Autodesk Fusion 360 part; units mm, degrees
(part 4 of 8)
  spline S80 degree 3 poles (3.437205, 4.752057) (3.428553, 4.734546) (3.423403, 4.715512) (3.42069, 4.676542) (3.423152, 4.656979) (3.435437, 4.619896) (3.445142, 4.602732) (3.470585, 4.573089) (3.48608, 4.560895) (3.520872, 4.543132) (3.539837, 4.537733) (3.578768, 4.534508) (3.598362, 4.536713) (3.62701, 4.545788) (3.636675, 4.55001) (3.654962, 4.560407) (3.663534, 4.566553) (3.671392, 4.573544) knots 0 0 0 0 0.00585967 0.00585967 0.01171933 0.01171933 0.017579 0.017579 0.02343867 0.02343867 0.02929834 0.02929834 0.035158 0.035158 0.03831344 0.03831344 0.04146887 0.04146887 0.04146887 0.04146887
  spline S81 degree 5 poles (3.437205, 4.752057) (3.437297, 4.752244) (3.438255, 4.754183) (3.440069, 4.75788) (3.442718, 4.763351) (3.446163, 4.770621) (3.45027, 4.779531) (3.454293, 4.788497) (3.458241, 4.797513) (3.462123, 4.806574) (3.465948, 4.815673) (3.469718, 4.824809) (3.473434, 4.833981) (3.477094, 4.843189) (3.480698, 4.852435) (3.484243, 4.861719) (3.48773, 4.871041) (3.491161, 4.8804) (3.494537, 4.889793) (3.49786, 4.89922) (3.501134, 4.908679) (3.504358, 4.91817) (3.507533, 4.927692) (3.510659, 4.937244) (3.513737, 4.946827) (3.516767, 4.956439) (3.519748, 4.966082) (3.522682, 4.975754) (3.525569, 4.985455) (3.528411, 4.995184) (3.531207, 5.00494) (3.533958, 5.014723) (3.536665, 5.024534) (3.539327, 5.03437) (3.541946, 5.044233) (3.544521, 5.054122) (3.547053, 5.064037) (3.549542, 5.073976) (3.551988, 5.083941) (3.554392, 5.09393) (3.556754, 5.103943) (3.559075, 5.11398) (3.561354, 5.124041) (3.563592, 5.134125) (3.565789, 5.144233) (3.567945, 5.154363) (3.570062, 5.164516) (3.572137, 5.174692) (3.574173, 5.18489) (3.576169, 5.195109) (3.578126, 5.20535) (3.580043, 5.215613) (3.581921, 5.225897) (3.58376, 5.236202) (3.58556, 5.246528) (3.587321, 5.256875) (3.589044, 5.267242) (3.590728, 5.277629) (3.592375, 5.288036) (3.593983, 5.298463) (3.595553, 5.30891) (3.597086, 5.319376) (3.59858, 5.329861) (3.599746, 5.338265) (3.600604, 5.344576) (3.601168, 5.348788) (3.601448, 5.350894) knots 0.1270499 0.1270499 0.1270499 0.1270499 0.1270499 0.1270499 0.12857143 0.14285714 0.15714286 0.17142857 0.18571429 0.2 0.21428571 0.22857143 0.24285714 0.25714286 0.27142857 0.28571429 0.3 0.31428571 0.32857143 0.34285714 0.35714286 0.37142857 0.38571429 0.4 0.41428571 0.42857143 0.44285714 0.45714286 0.47142857 0.48571429 0.5 0.51428571 0.52857143 0.54285714 0.55714286 0.57142857 0.58571429 0.6 0.61428571 0.62857143 0.64285714 0.65714286 0.67142857 0.68571429 0.7 0.71428571 0.72857143 0.74285714 0.75714286 0.77142857 0.78571429 0.8 0.81428571 0.82857143 0.84285714 0.85714286 0.87142857 0.88571429 0.9 0.91428571 0.92857143 0.94285714 0.95714286 0.97142857 0.98571429 1 1 1 1 1 1
  arc A27 (3.601448, 5.350894) -> (3.409471, 5.475218) centre (0, 0) ccw
  spline S82 degree 5 poles (3.409471, 5.475218) (3.407663, 5.4741) (3.404051, 5.471863) (3.398643, 5.468498) (3.391451, 5.463997) (3.382495, 5.458343) (3.373571, 5.452664) (3.364681, 5.446957) (3.355824, 5.441224) (3.347001, 5.435465) (3.338212, 5.429679) (3.329457, 5.423866) (3.320736, 5.418026) (3.31205, 5.41216) (3.303398, 5.406266) (3.294782, 5.400346) (3.286202, 5.394398) (3.277657, 5.388424) (3.269148, 5.382422) (3.260676, 5.376392) (3.25224, 5.370336) (3.243841, 5.364252) (3.235479, 5.35814) (3.227154, 5.352) (3.218868, 5.345833) (3.21062, 5.339637) (3.20241, 5.333414) (3.194239, 5.327162) (3.186107, 5.320882) (3.178016, 5.314574) (3.169964, 5.308237) (3.161952, 5.301871) (3.153982, 5.295476) (3.146054, 5.289052) (3.138167, 5.282598) (3.130322, 5.276115) (3.12252, 5.269603) (3.114761, 5.26306) (3.107046, 5.256488) (3.099375, 5.249885) (3.091749, 5.243251) (3.08417, 5.236586) (3.076637, 5.22989) (3.069152, 5.223161) (3.061715, 5.216401) (3.054325, 5.209608) (3.046984, 5.202784) (3.039691, 5.195928) (3.032449, 5.189038) (3.025258, 5.182115) (3.018122, 5.175157) (3.011042, 5.168161) (3.00402, 5.161129) (2.997057, 5.154058) (2.990152, 5.146951) (2.983303, 5.139808) (2.976508, 5.13263) (2.96977, 5.125418) (2.963091, 5.118169) (2.956478, 5.110879) (2.949942, 5.10354) (2.943491, 5.096148) (2.938267, 5.09003) (2.934359, 5.085375) (2.931727, 5.082207) (2.930349, 5.08054) (2.930217, 5.08038) knots -1 -1 -1 -1 -1 -1 -0.98571429 -0.97142857 -0.95714286 -0.94285714 -0.92857143 -0.91428571 -0.9 -0.88571429 -0.87142857 -0.85714286 -0.84285714 -0.82857143 -0.81428571 -0.8 -0.78571429 -0.77142857 -0.75714286 -0.74285714 -0.72857143 -0.71428571 -0.7 -0.68571429 -0.67142857 -0.65714286 -0.64285714 -0.62857143 -0.61428571 -0.6 -0.58571429 -0.57142857 -0.55714286 -0.54285714 -0.52857143 -0.51428571 -0.5 -0.48571429 -0.47142857 -0.45714286 -0.44285714 -0.42857143 -0.41428571 -0.4 -0.38571429 -0.37142857 -0.35714286 -0.34285714 -0.32857143 -0.31428571 -0.3 -0.28571429 -0.27142857 -0.25714286 -0.24285714 -0.22857143 -0.21428571 -0.2 -0.18571429 -0.17142857 -0.15714286 -0.14285714 -0.12857143 -0.1270499 -0.1270499 -0.1270499 -0.1270499 -0.1270499 -0.1270499
  spline S83 degree 3 poles (2.671525, 5.221052) (2.665646, 5.202425) (2.663463, 5.182829) (2.66673, 5.143901) (2.672149, 5.124942) (2.689951, 5.09017) (2.702162, 5.074688) (2.731833, 5.049277) (2.749007, 5.039591) (2.786103, 5.027347) (2.80567, 5.024906) (2.844637, 5.027662) (2.863665, 5.032832) (2.890591, 5.046174) (2.899499, 5.051822) (2.915985, 5.064889) (2.923518, 5.072271) (2.930217, 5.08038) knots 0 0 0 0 0.00585967 0.00585967 0.01171933 0.01171933 0.017579 0.017579 0.02343867 0.02343867 0.02929834 0.02929834 0.035158 0.035158 0.03831344 0.03831344 0.04146887 0.04146887 0.04146887 0.04146887
  spline S84 degree 5 poles (2.671525, 5.221052) (2.671587, 5.221251) (2.672237, 5.223313) (2.673466, 5.227244) (2.675248, 5.233055) (2.677544, 5.240765) (2.680242, 5.250198) (2.682849, 5.259673) (2.685375, 5.269187) (2.687828, 5.278733) (2.690219, 5.28831) (2.69255, 5.297914) (2.694823, 5.307546) (2.697035, 5.317205) (2.699185, 5.326893) (2.701271, 5.336609) (2.703294, 5.346354) (2.705256, 5.356127) (2.707159, 5.365925) (2.709004, 5.375749) (2.710796, 5.385597) (2.712533, 5.395469) (2.714218, 5.405364) (2.715849, 5.415281) (2.717428, 5.425221) (2.718955, 5.435184) (2.720429, 5.445169) (2.721852, 5.455175) (2.723225, 5.465203) (2.724548, 5.475251) (2.725822, 5.48532) (2.727047, 5.495409) (2.728225, 5.505518) (2.729355, 5.515646) (2.730437, 5.525793) (2.731472, 5.535959) (2.732461, 5.546143) (2.733404, 5.556346) (2.7343, 5.566567) (2.735151, 5.576806) (2.735957, 5.587063) (2.736718, 5.597337) (2.737435, 5.607628) (2.738107, 5.617935) (2.738736, 5.62826) (2.739321, 5.638601) (2.739862, 5.648958) (2.74036, 5.659331) (2.740816, 5.66972) (2.741228, 5.680124) (2.741599, 5.690544) (2.741927, 5.700979) (2.742213, 5.711429) (2.742457, 5.721894) (2.74266, 5.732374) (2.742821, 5.742868) (2.742941, 5.753377) (2.74302, 5.763899) (2.743058, 5.774436) (2.743056, 5.784986) (2.743013, 5.79555) (2.74293, 5.806127) (2.742807, 5.816718) (2.742677, 5.825201) (2.742561, 5.83157) (2.742475, 5.835818) (2.742431, 5.837943) knots 0.1270499 0.1270499 0.1270499 0.1270499 0.1270499 0.1270499 0.12857143 0.14285714 0.15714286 0.17142857 0.18571429 0.2 0.21428571 0.22857143 0.24285714 0.25714286 0.27142857 0.28571429 0.3 0.31428571 0.32857143 0.34285714 0.35714286 0.37142857 0.38571429 0.4 0.41428571 0.42857143 0.44285714 0.45714286 0.47142857 0.48571429 0.5 0.51428571 0.52857143 0.54285714 0.55714286 0.57142857 0.58571429 0.6 0.61428571 0.62857143 0.64285714 0.65714286 0.67142857 0.68571429 0.7 0.71428571 0.72857143 0.74285714 0.75714286 0.77142857 0.78571429 0.8 0.81428571 0.82857143 0.84285714 0.85714286 0.87142857 0.88571429 0.9 0.91428571 0.92857143 0.94285714 0.95714286 0.97142857 0.98571429 1 1 1 1 1 1
  arc A28 (2.742431, 5.837943) -> (2.533725, 5.931504) centre (0, 0) ccw
  spline S85 degree 5 poles (2.533725, 5.931504) (2.532109, 5.930123) (2.528881, 5.927361) (2.52405, 5.92321) (2.517629, 5.917664) (2.509641, 5.910709) (2.501689, 5.903734) (2.493774, 5.896737) (2.485896, 5.88972) (2.478056, 5.882681) (2.470253, 5.875621) (2.462488, 5.86854) (2.45476, 5.861437) (2.447072, 5.854314) (2.439421, 5.847169) (2.43181, 5.840002) (2.424238, 5.832815) (2.416705, 5.825606) (2.409212, 5.818375) (2.40176, 5.811123) (2.394347, 5.80385) (2.386975, 5.796555) (2.379644, 5.789238) (2.372355, 5.7819) (2.365107, 5.77454) (2.357901, 5.767158) (2.350737, 5.759754) (2.343616, 5.752329) (2.336539, 5.744881) (2.329505, 5.737411) (2.322515, 5.729919) (2.315569, 5.722405) (2.308668, 5.714868) (2.301813, 5.707309) (2.295004, 5.699727) (2.288241, 5.692123) (2.281524, 5.684496) (2.274855, 5.676846) (2.268233, 5.669172) (2.26166, 5.661476) (2.255137, 5.653756) (2.248664, 5.646012) (2.242242, 5.638244) (2.235871, 5.630452) (2.229553, 5.622635) (2.223287, 5.614794) (2.217073, 5.606929) (2.210913, 5.59904) (2.204807, 5.591126) (2.198757, 5.583186) (2.192767, 5.57522) (2.186838, 5.567226) (2.180972, 5.559204) (2.17517, 5.551153) (2.16943, 5.543075) (2.163752, 5.534971) (2.158133, 5.52684) (2.152574, 5.518684) (2.147079, 5.5105) (2.141658, 5.502286) (2.136318, 5.494035) (2.131072, 5.485745) (2.126843, 5.478901) (2.12369, 5.473704) (2.121573, 5.470172) (2.120466, 5.468314) (2.120359, 5.468135) knots -1 -1 -1 -1 -1 -1 -0.98571429 -0.97142857 -0.95714286 -0.94285714 -0.92857143 -0.91428571 -0.9 -0.88571429 -0.87142857 -0.85714286 -0.84285714 -0.82857143 -0.81428571 -0.8 -0.78571429 -0.77142857 -0.75714286 -0.74285714 -0.72857143 -0.71428571 -0.7 -0.68571429 -0.67142857 -0.65714286 -0.64285714 -0.62857143 -0.61428571 -0.6 -0.58571429 -0.57142857 -0.55714286 -0.54285714 -0.52857143 -0.51428571 -0.5 -0.48571429 -0.47142857 -0.45714286 -0.44285714 -0.42857143 -0.41428571 -0.4 -0.38571429 -0.37142857 -0.35714286 -0.34285714 -0.32857143 -0.31428571 -0.3 -0.28571429 -0.27142857 -0.25714286 -0.24285714 -0.22857143 -0.21428571 -0.2 -0.18571429 -0.17142857 -0.15714286 -0.14285714 -0.12857143 -0.1270499 -0.1270499 -0.1270499 -0.1270499 -0.1270499 -0.1270499
  spline S86 degree 3 poles (1.843226, 5.56767) (1.84026, 5.548364) (1.841093, 5.528664) (1.850264, 5.490691) (1.858514, 5.472782) (1.881415, 5.441134) (1.895847, 5.427698) (1.929048, 5.407114) (1.9475, 5.400163) (1.986031, 5.393725) (2.00574, 5.3943) (2.04383, 5.402972) (2.061846, 5.410986) (2.08642, 5.428282) (2.094361, 5.435223) (2.108659, 5.450653) (2.114977, 5.459099) (2.120359, 5.468135) knots 0 0 0 0 0.00585967 0.00585967 0.01171933 0.01171933 0.017579 0.017579 0.02343867 0.02343867 0.02929834 0.02929834 0.035158 0.035158 0.03831344 0.03831344 0.04146887 0.04146887 0.04146887 0.04146887
  spline S87 degree 5 poles (1.843226, 5.56767) (1.843257, 5.567876) (1.843585, 5.570013) (1.844199, 5.574086) (1.845073, 5.580101) (1.846165, 5.588071) (1.847392, 5.597805) (1.848522, 5.607567) (1.849566, 5.617354) (1.850533, 5.627164) (1.851434, 5.636993) (1.852272, 5.64684) (1.853048, 5.656706) (1.853759, 5.66659) (1.854405, 5.676493) (1.854984, 5.686414) (1.855496, 5.696353) (1.855943, 5.706311) (1.856327, 5.716285) (1.856652, 5.726275) (1.856919, 5.736281) (1.857129, 5.746303) (1.857283, 5.756338) (1.857382, 5.766389) (1.857425, 5.776453) (1.857413, 5.786532) (1.857346, 5.796625) (1.857225, 5.806732) (1.857051, 5.816851) (1.856824, 5.826984) (1.856546, 5.837129) (1.856217, 5.847287) (1.855838, 5.857457) (1.855408, 5.867639) (1.854929, 5.877832) (1.854401, 5.888037) (1.853823, 5.898253) (1.853197, 5.90848) (1.852523, 5.918719) (1.851801, 5.928968) (1.851032, 5.939227) (1.850216, 5.949496) (1.849353, 5.959776) (1.848444, 5.970066) (1.847489, 5.980365) (1.846489, 5.990674) (1.845443, 6.000992) (1.844352, 6.01132) (1.843216, 6.021657) (1.842035, 6.032002) (1.840811, 6.042356) (1.839542, 6.052719) (1.83823, 6.063091) (1.836874, 6.07347) (1.835474, 6.083858) (1.834032, 6.094254) (1.832546, 6.104658) (1.831018, 6.115069) (1.829447, 6.125488) (1.827835, 6.135914) (1.82618, 6.146348) (1.824483, 6.156788) (1.822745, 6.167236) (1.821321, 6.1756) (1.820234, 6.181876) (1.819501, 6.186061) (1.819133, 6.188155) knots 0.1270499 0.1270499 0.1270499 0.1270499 0.1270499 0.1270499 0.12857143 0.14285714 0.15714286 0.17142857 0.18571429 0.2 0.21428571 0.22857143 0.24285714 0.25714286 0.27142857 0.28571429 0.3 0.31428571 0.32857143 0.34285714 0.35714286 0.37142857 0.38571429 0.4 0.41428571 0.42857143 0.44285714 0.45714286 0.47142857 0.48571429 0.5 0.51428571 0.52857143 0.54285714 0.55714286 0.57142857 0.58571429 0.6 0.61428571 0.62857143 0.64285714 0.65714286 0.67142857 0.68571429 0.7 0.71428571 0.72857143 0.74285714 0.75714286 0.77142857 0.78571429 0.8 0.81428571 0.82857143 0.84285714 0.85714286 0.87142857 0.88571429 0.9 0.91428571 0.92857143 0.94285714 0.95714286 0.97142857 0.98571429 1 1 1 1 1 1
  arc A29 (1.819133, 6.188155) -> (1.598591, 6.24876) centre (0, 0) ccw
  spline S88 degree 5 poles (1.598591, 6.24876) (1.597205, 6.247149) (1.594436, 6.243926) (1.590295, 6.239087) (1.584797, 6.232625) (1.577963, 6.224533) (1.57117, 6.216426) (1.564416, 6.208303) (1.557701, 6.200165) (1.551027, 6.192012) (1.544393, 6.183843) (1.5378, 6.17566) (1.531247, 6.167461) (1.524736, 6.159247) (1.518266, 6.151018) (1.511838, 6.142774) (1.505452, 6.134515) (1.499108, 6.12624) (1.492807, 6.117951) (1.486548, 6.109646) (1.480333, 6.101326) (1.474161, 6.092992) (1.468033, 6.084642) (1.461949, 6.076277) (1.455909, 6.067896) (1.449915, 6.059501) (1.443965, 6.051091) (1.438061, 6.042665) (1.432203, 6.034224) (1.426392, 6.025768) (1.420628, 6.017297) (1.41491, 6.008811) (1.409241, 6.000309) (1.40362, 5.991792) (1.398048, 5.98326) (1.392525, 5.974712) (1.387052, 5.966149) (1.381628, 5.95757) (1.376255, 5.948976) (1.370934, 5.940367) (1.365666, 5.931741) (1.360451, 5.9231) (1.35529, 5.914443) (1.350183, 5.905769) (1.345132, 5.89708) (1.340136, 5.888375) (1.335196, 5.879653) (1.330312, 5.870916) (1.325486, 5.862163) (1.320719, 5.853393) (1.316015, 5.844605) (1.311376, 5.8358) (1.306803, 5.826976) (1.302298, 5.818134) (1.297859, 5.809275) (1.293484, 5.800398) (1.289172, 5.791505) (1.284924, 5.782596) (1.280743, 5.77367) (1.276638, 5.764724) (1.272621, 5.755755) (1.268701, 5.746761) (1.265567, 5.739352) (1.263245, 5.733735) (1.261691, 5.72992) (1.260881, 5.727916) (1.260803, 5.727723) knots -1 -1 -1 -1 -1 -1 -0.98571429 -0.97142857 -0.95714286 -0.94285714 -0.92857143 -0.91428571 -0.9 -0.88571429 -0.87142857 -0.85714286 -0.84285714 -0.82857143 -0.81428571 -0.8 -0.78571429 -0.77142857 -0.75714286 -0.74285714 -0.72857143 -0.71428571 -0.7 -0.68571429 -0.67142857 -0.65714286 -0.64285714 -0.62857143 -0.61428571 -0.6 -0.58571429 -0.57142857 -0.55714286 -0.54285714 -0.52857143 -0.51428571 -0.5 -0.48571429 -0.47142857 -0.45714286 -0.44285714 -0.42857143 -0.41428571 -0.4 -0.38571429 -0.37142857 -0.35714286 -0.34285714 -0.32857143 -0.31428571 -0.3 -0.28571429 -0.27142857 -0.25714286 -0.24285714 -0.22857143 -0.21428571 -0.2 -0.18571429 -0.17142857 -0.15714286 -0.14285714 -0.12857143 -0.1270499 -0.1270499 -0.1270499 -0.1270499 -0.1270499 -0.1270499
  spline S89 degree 3 poles (0.971723, 5.783786) (0.971739, 5.764254) (0.97557, 5.744912) (0.99043, 5.708784) (1.001317, 5.692344) (1.02878, 5.664563) (1.045094, 5.653487) (1.081048, 5.638213) (1.100345, 5.63416) (1.139407, 5.633679) (1.158798, 5.637256) (1.195117, 5.65164) (1.211699, 5.662311) (1.233345, 5.683155) (1.240133, 5.691227) (1.251908, 5.708659) (1.256863, 5.71797) (1.260803, 5.727723) knots 0 0 0 0 0.00585967 0.00585967 0.01171933 0.01171933 0.017579 0.017579 0.02343867 0.02343867 0.02929834 0.02929834 0.035158 0.035158 0.03831344 0.03831344 0.04146887 0.04146887 0.04146887 0.04146887
  spline S90 degree 5 poles (0.971723, 5.783786) (0.971723, 5.783994) (0.97172, 5.786157) (0.971705, 5.790275) (0.971652, 5.796353) (0.971514, 5.804397) (0.97124, 5.814204) (0.970867, 5.824024) (0.970404, 5.833856) (0.969863, 5.843698) (0.969253, 5.85355) (0.968578, 5.86341) (0.967839, 5.873278) (0.967033, 5.883155) (0.96616, 5.89304) (0.965217, 5.902933) (0.964206, 5.912834) (0.963128, 5.922743) (0.961985, 5.932659) (0.960781, 5.942582) (0.959517, 5.952512) (0.958195, 5.962448) (0.956816, 5.972389) (0.955379, 5.982337) (0.953885, 5.99229) (0.952335, 6.002249) (0.950728, 6.012214) (0.949065, 6.022183) (0.947349, 6.032158) (0.945578, 6.042137) (0.943755, 6.052121) (0.941879, 6.06211) (0.939952, 6.072102) (0.937973, 6.082099) (0.935943, 6.0921) (0.933863, 6.102105) (0.931733, 6.112113) (0.929553, 6.122125) (0.927324, 6.13214) (0.925046, 6.142159) (0.92272, 6.15218) (0.920346, 6.162205) (0.917924, 6.172233) (0.915455, 6.182263) (0.912939, 6.192296) (0.910377, 6.202331) (0.907768, 6.212369) (0.905113, 6.222409) (0.902413, 6.232451) (0.899667, 6.242495) (0.896876, 6.252541) (0.89404, 6.262589) (0.89116, 6.272638) (0.888235, 6.282689) (0.885267, 6.292742) (0.882254, 6.302795) (0.879198, 6.31285) (0.876098, 6.322907) (0.872956, 6.332964) (0.86977, 6.343022) (0.866542, 6.35308) (0.863272, 6.363139) (0.859959, 6.373199) (0.857275, 6.381248) (0.855243, 6.387284) (0.85388, 6.391309) (0.853196, 6.393321) knots 0.1270499 0.1270499 0.1270499 0.1270499 0.1270499 0.1270499 0.12857143 0.14285714 0.15714286 0.17142857 0.18571429 0.2 0.21428571 0.22857143 0.24285714 0.25714286 0.27142857 0.28571429 0.3 0.31428571 0.32857143 0.34285714 0.35714286 0.37142857 0.38571429 0.4 0.41428571 0.42857143 0.44285714 0.45714286 0.47142857 0.48571429 0.5 0.51428571 0.52857143 0.54285714 0.55714286 0.57142857 0.58571429 0.6 0.61428571 0.62857143 0.64285714 0.65714286 0.67142857 0.68571429 0.7 0.71428571 0.72857143 0.74285714 0.75714286 0.77142857 0.78571429 0.8 0.81428571 0.82857143 0.84285714 0.85714286 0.87142857 0.88571429 0.9 0.91428571 0.92857143 0.94285714 0.95714286 0.97142857 0.98571429 1 1 1 1 1 1
  arc A30 (0.853196, 6.393321) -> (0.625988, 6.419551) centre (0, 0) ccw
  spline S91 degree 5 poles (0.625988, 6.419551) (0.624864, 6.417748) (0.622619, 6.41414) (0.619265, 6.408725) (0.614818, 6.4015) (0.6093, 6.392459) (0.603823, 6.38341) (0.598388, 6.374351) (0.592995, 6.365284) (0.587643, 6.356207) (0.582334, 6.347122) (0.577067, 6.338028) (0.571843, 6.328925) (0.566662, 6.319813) (0.561524, 6.310693) (0.55643, 6.301564) (0.551379, 6.292427) (0.546373, 6.283281) (0.541411, 6.274127) (0.536493, 6.264964) (0.531621, 6.255793) (0.526793, 6.246614) (0.522012, 6.237426) (0.517276, 6.228231) (0.512587, 6.219027) (0.507944, 6.209815) (0.503348, 6.200595) (0.498799, 6.191367) (0.494299, 6.182131) (0.489846, 6.172887) (0.485442, 6.163635) (0.481088, 6.154375) (0.476783, 6.145108) (0.472528, 6.135832) (0.468323, 6.126549) (0.46417, 6.117259) (0.460068, 6.107961) (0.456017, 6.098655) (0.452019, 6.089341) (0.448075, 6.08002) (0.444185, 6.070692) (0.44035, 6.061356) (0.436571, 6.052012) (0.432848, 6.042661) (0.429183, 6.033302) (0.425574, 6.023936) (0.422023, 6.014563) (0.41853, 6.005183) (0.415097, 5.995795) (0.411725, 5.9864) (0.408417, 5.976998) (0.405176, 5.967587) (0.402004, 5.958169) (0.398902, 5.948743) (0.395867, 5.93931) (0.392898, 5.929869) (0.389994, 5.920422) (0.387156, 5.910969) (0.384386, 5.901509) (0.381696, 5.892041) (0.379095, 5.882565) (0.376594, 5.873077) (0.374627, 5.865277) (0.373189, 5.859371) (0.372236, 5.855364) (0.371741, 5.853259) (0.371694, 5.853057) knots -1 -1 -1 -1 -1 -1 -0.98571429 -0.97142857 -0.95714286 -0.94285714 -0.92857143 -0.91428571 -0.9 -0.88571429 -0.87142857 -0.85714286 -0.84285714 -0.82857143 -0.81428571 -0.8 -0.78571429 -0.77142857 -0.75714286 -0.74285714 -0.72857143 -0.71428571 -0.7 -0.68571429 -0.67142857 -0.65714286 -0.64285714 -0.62857143 -0.61428571 -0.6 -0.58571429 -0.57142857 -0.55714286 -0.54285714 -0.52857143 -0.51428571 -0.5 -0.48571429 -0.47142857 -0.45714286 -0.44285714 -0.42857143 -0.41428571 -0.4 -0.38571429 -0.37142857 -0.35714286 -0.34285714 -0.32857143 -0.31428571 -0.3 -0.28571429 -0.27142857 -0.25714286 -0.24285714 -0.22857143 -0.21428571 -0.2 -0.18571429 -0.17142857 -0.15714286 -0.14285714 -0.12857143 -0.1270499 -0.1270499 -0.1270499 -0.1270499 -0.1270499 -0.1270499
  spline S92 degree 3 poles (0.077444, 5.864336) (0.080441, 5.845035) (0.08718, 5.826504) (0.10738, 5.793068) (0.12065, 5.778483) (0.152032, 5.755219) (0.169845, 5.746764) (0.20771, 5.737157) (0.227399, 5.736097) (0.266077, 5.741584) (0.284694, 5.748079) (0.318392, 5.767839) (0.33315, 5.780916) (0.351361, 5.80482) (0.356837, 5.813834) (0.365814, 5.832859) (0.369289, 5.842817) (0.371694, 5.853057) knots 0 0 0 0 0.00585967 0.00585967 0.01171933 0.01171933 0.017579 0.017579 0.02343867 0.02343867 0.02929834 0.02929834 0.035158 0.035158 0.03831344 0.03831344 0.04146887 0.04146887 0.04146887 0.04146887
  spline S93 degree 5 poles (0.077444, 5.864336) (0.077412, 5.864541) (0.07708, 5.866678) (0.076436, 5.870746) (0.075455, 5.876745) (0.074091, 5.884673) (0.072323, 5.894323) (0.070456, 5.903971) (0.068498, 5.913617) (0.066461, 5.923262) (0.064354, 5.932905) (0.062182, 5.942546) (0.059944, 5.952186) (0.057641, 5.961824) (0.055269, 5.97146) (0.052827, 5.981093) (0.050316, 5.990724) (0.047738, 6.000352) (0.045095, 6.009978) (0.04239, 6.0196) (0.039625, 6.029221) (0.036802, 6.038838) (0.033921, 6.048453) (0.030983, 6.058065) (0.027987, 6.067673) (0.024935, 6.077279) (0.021826, 6.086881) (0.018661, 6.09648) (0.015441, 6.106076) (0.012168, 6.115668) (0.008842, 6.125256) (0.005464, 6.134841) (0.002034, 6.144423) (-0.001448, 6.154) (-0.00498, 6.163574) (-0.008563, 6.173144) (-0.012196, 6.18271) (-0.015879, 6.192272) (-0.019611, 6.201829) (-0.023391, 6.211383) (-0.02722, 6.220932) (-0.031097, 6.230477) (-0.035021, 6.240017) (-0.038992, 6.249553) (-0.04301, 6.259084) (-0.047074, 6.268611) (-0.051185, 6.278133) (-0.055341, 6.28765) (-0.059542, 6.297162) (-0.063789, 6.306669) (-0.068081, 6.316171) (-0.072417, 6.325669) (-0.076798, 6.33516) (-0.081223, 6.344647) (-0.085691, 6.354129) (-0.090203, 6.363605) (-0.094758, 6.373075) (-0.099356, 6.382541) (-0.103997, 6.392) (-0.108681, 6.401454) (-0.113406, 6.410902) (-0.118174, 6.420344) (-0.122984, 6.42978) (-0.126865, 6.437325) (-0.129795, 6.44298) (-0.131756, 6.44675) (-0.132739, 6.448634) knots 0.1270499 0.1270499 0.1270499 0.1270499 0.1270499 0.1270499 0.12857143 0.14285714 0.15714286 0.17142857 0.18571429 0.2 0.21428571 0.22857143 0.24285714 0.25714286 0.27142857 0.28571429 0.3 0.31428571 0.32857143 0.34285714 0.35714286 0.37142857 0.38571429 0.4 0.41428571 0.42857143 0.44285714 0.45714286 0.47142857 0.48571429 0.5 0.51428571 0.52857143 0.54285714 0.55714286 0.57142857 0.58571429 0.6 0.61428571 0.62857143 0.64285714 0.65714286 0.67142857 0.68571429 0.7 0.71428571 0.72857143 0.74285714 0.75714286 0.77142857 0.78571429 0.8 0.81428571 0.82857143 0.84285714 0.85714286 0.87142857 0.88571429 0.9 0.91428571 0.92857143 0.94285714 0.95714286 0.97142857 0.98571429 1 1 1 1 1 1
  arc A31 (-0.132739, 6.448634) -> (-0.361288, 6.439873) centre (0, 0) ccw
  spline S94 degree 5 poles (-0.361288, 6.439873) (-0.362124, 6.437919) (-0.363791, 6.434011) (-0.36628, 6.428148) (-0.369572, 6.420328) (-0.373645, 6.410552) (-0.377676, 6.400772) (-0.381665, 6.39099) (-0.385611, 6.381206) (-0.389514, 6.371419) (-0.393374, 6.361629) (-0.397191, 6.351838) (-0.400964, 6.342044) (-0.404694, 6.332248) (-0.408379, 6.322451) (-0.41202, 6.312651) (-0.415617, 6.30285) (-0.419169, 6.293047) (-0.422675, 6.283243) (-0.426137, 6.273437) (-0.429552, 6.26363) (-0.432922, 6.253821) (-0.436245, 6.244011) (-0.439521, 6.2342) (-0.442751, 6.224388) (-0.445933, 6.214576) (-0.449067, 6.204762) (-0.452154, 6.194948) (-0.455192, 6.185133) (-0.458181, 6.175318) (-0.461121, 6.165502) (-0.464012, 6.155686) (-0.466851, 6.14587) (-0.469641, 6.136054) (-0.472379, 6.126238) (-0.475065, 6.116422) (-0.4777, 6.106607) (-0.480282, 6.096792) (-0.482812, 6.086977) (-0.485287, 6.077163) (-0.487708, 6.06735) (-0.490073, 6.057538) (-0.492381, 6.047727) (-0.494632, 6.037917) (-0.496826, 6.028109) (-0.498963, 6.018302) (-0.501041, 6.008496) (-0.503061, 5.998693) (-0.505022, 5.988891) (-0.50692, 5.979092) (-0.508754, 5.969294) (-0.51052, 5.9595) (-0.512217, 5.949708) (-0.513845, 5.939918) (-0.515404, 5.930132) (-0.516897, 5.920349) (-0.518325, 5.91057) (-0.519687, 5.900794) (-0.52098, 5.891022) (-0.522193, 5.881255) (-0.523317, 5.871492) (-0.524341, 5.861734) (-0.525094, 5.853725) (-0.525613, 5.847669) (-0.525943, 5.843564) (-0.526111, 5.841408) (-0.526127, 5.8412) knots -1 -1 -1 -1 -1 -1 -0.98571429 -0.97142857 -0.95714286 -0.94285714 -0.92857143 -0.91428571 -0.9 -0.88571429 -0.87142857 -0.85714286 -0.84285714 -0.82857143 -0.81428571 -0.8 -0.78571429 -0.77142857 -0.75714286 -0.74285714 -0.72857143 -0.71428571 -0.7 -0.68571429 -0.67142857 -0.65714286 -0.64285714 -0.62857143 -0.61428571 -0.6 -0.58571429 -0.57142857 -0.55714286 -0.54285714 -0.52857143 -0.51428571 -0.5 -0.48571429 -0.47142857 -0.45714286 -0.44285714 -0.42857143 -0.41428571 -0.4 -0.38571429 -0.37142857 -0.35714286 -0.34285714 -0.32857143 -0.31428571 -0.3 -0.28571429 -0.27142857 -0.25714286 -0.24285714 -0.22857143 -0.21428571 -0.2 -0.18571429 -0.17142857 -0.15714286 -0.14285714 -0.12857143 -0.1270499 -0.1270499 -0.1270499 -0.1270499 -0.1270499 -0.1270499
  spline S95 degree 3 poles (-0.81865, 5.80743) (-0.812742, 5.788813) (-0.803254, 5.771527) (-0.778186, 5.741567) (-0.762845, 5.729178) (-0.72828, 5.710978) (-0.709385, 5.705341) (-0.670497, 5.701626) (-0.650877, 5.703585) (-0.61349, 5.714912) (-0.596082, 5.724172) (-0.565796, 5.748845) (-0.553207, 5.764021) (-0.538858, 5.790425) (-0.534822, 5.800169) (-0.528855, 5.820342) (-0.526941, 5.830714) (-0.526127, 5.8412) knots 0 0 0 0 0.00585967 0.00585967 0.01171933 0.01171933 0.017579 0.017579 0.02343867 0.02343867 0.02929834 0.02929834 0.035158 0.035158 0.03831344 0.03831344 0.04146887 0.04146887 0.04146887 0.04146887
  spline S96 degree 5 poles (-0.81865, 5.80743) (-0.818713, 5.807628) (-0.819368, 5.809689) (-0.820625, 5.813611) (-0.82251, 5.81939) (-0.825068, 5.827017) (-0.828288, 5.836284) (-0.831607, 5.845534) (-0.835015, 5.854768) (-0.8385, 5.863989) (-0.842054, 5.873197) (-0.845673, 5.882394) (-0.849355, 5.891579) (-0.853103, 5.900753) (-0.856918, 5.909913) (-0.860802, 5.919061) (-0.864753, 5.928196) (-0.868771, 5.937318) (-0.872852, 5.946427) (-0.876995, 5.955524) (-0.881195, 5.964609) (-0.885454, 5.973683) (-0.889768, 5.982746) (-0.894139, 5.991796) (-0.898567, 6.000835) (-0.90305, 6.009862) (-0.907588, 6.018877) (-0.912181, 6.02788) (-0.916828, 6.036872) (-0.921527, 6.045852) (-0.926277, 6.054821) (-0.931079, 6.063778) (-0.935932, 6.072723) (-0.940835, 6.081657) (-0.945787, 6.090579) (-0.950789, 6.09949) (-0.95584, 6.108389) (-0.960939, 6.117277) (-0.966086, 6.126153) (-0.97128, 6.135017) (-0.976522, 6.14387) (-0.98181, 6.152711) (-0.987144, 6.161541) (-0.992525, 6.170359) (-0.99795, 6.179165) (-1.003421, 6.187959) (-1.008937, 6.196742) (-1.014497, 6.205513) (-1.020102, 6.214273) (-1.02575, 6.22302) (-1.031442, 6.231756) (-1.037177, 6.24048) (-1.042956, 6.249192) (-1.048776, 6.257892) (-1.05464, 6.26658) (-1.060545, 6.275257) (-1.066493, 6.283921) (-1.072482, 6.292573) (-1.078513, 6.301213) (-1.084584, 6.309841) (-1.090697, 6.318457) (-1.09685, 6.327061) (-1.103044, 6.335653) (-1.108031, 6.342516) (-1.11179, 6.347658) (-1.114304, 6.351084) (-1.115563, 6.352796) knots 0.1270499 0.1270499 0.1270499 0.1270499 0.1270499 0.1270499 0.12857143 0.14285714 0.15714286 0.17142857 0.18571429 0.2 0.21428571 0.22857143 0.24285714 0.25714286 0.27142857 0.28571429 0.3 0.31428571 0.32857143 0.34285714 0.35714286 0.37142857 0.38571429 0.4 0.41428571 0.42857143 0.44285714 0.45714286 0.47142857 0.48571429 0.5 0.51428571 0.52857143 0.54285714 0.55714286 0.57142857 0.58571429 0.6 0.61428571 0.62857143 0.64285714 0.65714286 0.67142857 0.68571429 0.7 0.71428571 0.72857143 0.74285714 0.75714286 0.77142857 0.78571429 0.8 0.81428571 0.82857143 0.84285714 0.85714286 0.87142857 0.88571429 0.9 0.91428571 0.92857143 0.94285714 0.95714286 0.97142857 0.98571429 1 1 1 1 1 1
  arc A32 (-1.115563, 6.352796) -> (-1.340096, 6.30925) centre (0, 0) ccw
  spline S97 degree 5 poles (-1.340096, 6.30925) (-1.340624, 6.307192) (-1.341675, 6.303075) (-1.343239, 6.2969) (-1.345299, 6.28867) (-1.347832, 6.278386) (-1.350323, 6.268106) (-1.352772, 6.25783) (-1.355178, 6.247557) (-1.357541, 6.237289) (-1.359862, 6.227025) (-1.36214, 6.216766) (-1.364374, 6.206511) (-1.366564, 6.196261) (-1.368711, 6.186015) (-1.370813, 6.175775) (-1.372872, 6.16554) (-1.374885, 6.15531) (-1.376854, 6.145085) (-1.378778, 6.134865) (-1.380656, 6.124652) (-1.382489, 6.114444) (-1.384276, 6.104242) (-1.386016, 6.094045) (-1.38771, 6.083856) (-1.389357, 6.073672) (-1.390957, 6.063495) (-1.392509, 6.053325) (-1.394014, 6.043161) (-1.39547, 6.033005) (-1.396877, 6.022855) (-1.398235, 6.012713) (-1.399543, 6.002579) (-1.400801, 5.992452) (-1.402009, 5.982333) (-1.403165, 5.972222) (-1.404271, 5.962119) (-1.405325, 5.952025) (-1.406326, 5.94194) (-1.407274, 5.931863) (-1.408169, 5.921795) (-1.409008, 5.911737) (-1.409792, 5.901689) (-1.410519, 5.89165) (-1.41119, 5.881622) (-1.411804, 5.871604) (-1.412362, 5.861596) (-1.412862, 5.851599) (-1.413303, 5.841613) (-1.413683, 5.831638) (-1.414, 5.821676) (-1.41425, 5.811726) (-1.414433, 5.80179) (-1.414547, 5.791867) (-1.414594, 5.781958) (-1.414576, 5.772062) (-1.414494, 5.762179) (-1.414348, 5.75231) (-1.414134, 5.742455) (-1.413843, 5.732616) (-1.413463, 5.722796) (-1.412985, 5.712997) (-1.412507, 5.704967) (-1.412095, 5.698902) (-1.411795, 5.694795) (-1.411632, 5.692638) (-1.411616, 5.692431) knots -1 -1 -1 -1 -1 -1 -0.98571429 -0.97142857 -0.95714286 -0.94285714 -0.92857143 -0.91428571 -0.9 -0.88571429 -0.87142857 -0.85714286 -0.84285714 -0.82857143 -0.81428571 -0.8 -0.78571429 -0.77142857 -0.75714286 -0.74285714 -0.72857143 -0.71428571 -0.7 -0.68571429 -0.67142857 -0.65714286 -0.64285714 -0.62857143 -0.61428571 -0.6 -0.58571429 -0.57142857 -0.55714286 -0.54285714 -0.52857143 -0.51428571 -0.5 -0.48571429 -0.47142857 -0.45714286 -0.44285714 -0.42857143 -0.41428571 -0.4 -0.38571429 -0.37142857 -0.35714286 -0.34285714 -0.32857143 -0.31428571 -0.3 -0.28571429 -0.27142857 -0.25714286 -0.24285714 -0.22857143 -0.21428571 -0.2 -0.18571429 -0.17142857 -0.15714286 -0.14285714 -0.12857143 -0.1270499 -0.1270499 -0.1270499 -0.1270499 -0.1270499 -0.1270499
  spline S98 degree 3 poles (-1.695556, 5.614403) (-1.686875, 5.596906) (-1.674859, 5.581271) (-1.645512, 5.555489) (-1.62846, 5.545587) (-1.591521, 5.532877) (-1.571987, 5.53019) (-1.532989, 5.532455) (-1.513897, 5.537385) (-1.478678, 5.554286) (-1.462887, 5.566096) (-1.436722, 5.595103) (-1.426597, 5.612023) (-1.416447, 5.640307) (-1.413946, 5.650554) (-1.411128, 5.6714) (-1.41082, 5.681943) (-1.411616, 5.692431) knots 0 0 0 0 0.00585967 0.00585967 0.01171933 0.01171933 0.017579 0.017579 0.02343867 0.02343867 0.02929834 0.02929834 0.035158 0.035158 0.03831344 0.03831344 0.04146887 0.04146887 0.04146887 0.04146887
  spline S99 degree 5 poles (-1.695556, 5.614403) (-1.695649, 5.614589) (-1.69661, 5.616526) (-1.698451, 5.62021) (-1.701196, 5.625633) (-1.704889, 5.63278) (-1.709486, 5.641448) (-1.714178, 5.650083) (-1.718955, 5.658689) (-1.723807, 5.667269) (-1.728725, 5.675827) (-1.733705, 5.684363) (-1.738747, 5.692879) (-1.743851, 5.701373) (-1.74902, 5.709844) (-1.754254, 5.718292) (-1.759554, 5.726716) (-1.764917, 5.735117) (-1.770341, 5.743497) (-1.775823, 5.751855) (-1.781362, 5.760193) (-1.786955, 5.76851) (-1.792602, 5.776808) (-1.798304, 5.785085) (-1.804059, 5.793342) (-1.809868, 5.801579) (-1.815729, 5.809796) (-1.821642, 5.817992) (-1.827607, 5.82617) (-1.833622, 5.834327) (-1.839686, 5.842465) (-1.845799, 5.850584) (-1.85196, 5.858684) (-1.858169, 5.866765) (-1.864425, 5.874827) (-1.870729, 5.88287) (-1.877079, 5.890893) (-1.883475, 5.898898) (-1.889916, 5.906885) (-1.896403, 5.914852) (-1.902935, 5.922801) (-1.909511, 5.930731) (-1.91613, 5.938643) (-1.922793, 5.946537) (-1.9295, 5.954411) (-1.936249, 5.962268) (-1.943041, 5.970106) (-1.949875, 5.977925) (-1.956751, 5.985726) (-1.963669, 5.993509) (-1.970627, 6.001274) (-1.977627, 6.00902) (-1.984667, 6.016748) (-1.991748, 6.024457) (-1.998869, 6.032149) (-2.00603, 6.039822) (-2.01323, 6.047477) (-2.02047, 6.055113) (-2.027749, 6.062732) (-2.035066, 6.070332) (-2.042422, 6.077914) (-2.049817, 6.085477) (-2.057249, 6.093023) (-2.063226, 6.099044) (-2.067726, 6.103552) (-2.070733, 6.106554) (-2.072239, 6.108054) knots 0.1270499 0.1270499 0.1270499 0.1270499 0.1270499 0.1270499 0.12857143 0.14285714 0.15714286 0.17142857 0.18571429 0.2 0.21428571 0.22857143 0.24285714 0.25714286 0.27142857 0.28571429 0.3 0.31428571 0.32857143 0.34285714 0.35714286 0.37142857 0.38571429 0.4 0.41428571 0.42857143 0.44285714 0.45714286 0.47142857 0.48571429 0.5 0.51428571 0.52857143 0.54285714 0.55714286 0.57142857 0.58571429 0.6 0.61428571 0.62857143 0.64285714 0.65714286 0.67142857 0.68571429 0.7 0.71428571 0.72857143 0.74285714 0.75714286 0.77142857 0.78571429 0.8 0.81428571 0.82857143 0.84285714 0.85714286 0.87142857 0.88571429 0.9 0.91428571 0.92857143 0.94285714 0.95714286 0.97142857 0.98571429 1 1 1 1 1 1
  arc A33 (-2.072239, 6.108054) -> (-2.287494, 6.030744) centre (0, 0) ccw
  spline S100 degree 5 poles (-2.287494, 6.030744) (-2.287701, 6.028629) (-2.288111, 6.0244) (-2.288714, 6.018059) (-2.289494, 6.00961) (-2.290427, 5.99906) (-2.29132, 5.98852) (-2.292171, 5.977991) (-2.292981, 5.967472) (-2.293749, 5.956963) (-2.294476, 5.946465) (-2.295161, 5.935978) (-2.295803, 5.925503) (-2.296403, 5.915038) (-2.296961, 5.904585) (-2.297476, 5.894144) (-2.297947, 5.883714) (-2.298376, 5.873297) (-2.298761, 5.862891) (-2.299102, 5.852498) (-2.299399, 5.842117) (-2.299652, 5.831749) (-2.299861, 5.821394) (-2.300025, 5.811051) (-2.300143, 5.800722) (-2.300216, 5.790407) (-2.300244, 5.780105) (-2.300225, 5.769817) (-2.300161, 5.759543) (-2.300049, 5.749283) (-2.29989, 5.739038) (-2.299684, 5.728807) (-2.29943, 5.718592) (-2.299128, 5.708392) (-2.298776, 5.698207) (-2.298376, 5.688038) (-2.297927, 5.677885) (-2.297427, 5.667748) (-2.296877, 5.657628) (-2.296276, 5.647524) (-2.295623, 5.637438) (-2.294918, 5.62737) (-2.294158, 5.61732) (-2.293345, 5.607288) (-2.292477, 5.597274) (-2.291555, 5.58728) (-2.290578, 5.577304) (-2.289546, 5.567348) (-2.288458, 5.557412) (-2.287311, 5.547496) (-2.286103, 5.537602) (-2.284832, 5.527731) (-2.283495, 5.517883) (-2.282093, 5.508059) (-2.280627, 5.498259) (-2.279099, 5.488481) (-2.277509, 5.478727) (-2.275859, 5.468996) (-2.274143, 5.459289) (-2.272353, 5.44961) (-2.270479, 5.439964) (-2.268511, 5.430352) (-2.266812, 5.422489) (-2.26548, 5.416558) (-2.264556, 5.412545) (-2.264065, 5.410438) (-2.264018, 5.410236) knots -1 -1 -1 -1 -1 -1 -0.98571429 -0.97142857 -0.95714286 -0.94285714 -0.92857143 -0.91428571 -0.9 -0.88571429 -0.87142857 -0.85714286 -0.84285714 -0.82857143 -0.81428571 -0.8 -0.78571429 -0.77142857 -0.75714286 -0.74285714 -0.72857143 -0.71428571 -0.7 -0.68571429 -0.67142857 -0.65714286 -0.64285714 -0.62857143 -0.61428571 -0.6 -0.58571429 -0.57142857 -0.55714286 -0.54285714 -0.52857143 -0.51428571 -0.5 -0.48571429 -0.47142857 -0.45714286 -0.44285714 -0.42857143 -0.41428571 -0.4 -0.38571429 -0.37142857 -0.35714286 -0.34285714 -0.32857143 -0.31428571 -0.3 -0.28571429 -0.27142857 -0.25714286 -0.24285714 -0.22857143 -0.21428571 -0.2 -0.18571429 -0.17142857 -0.15714286 -0.14285714 -0.12857143 -0.1270499 -0.1270499 -0.1270499 -0.1270499 -0.1270499 -0.1270499
  spline S101 degree 3 poles (-2.532719, 5.289779) (-2.521469, 5.273812) (-2.507208, 5.260195) (-2.474268, 5.239195) (-2.455905, 5.232012) (-2.417459, 5.225089) (-2.397744, 5.225415) (-2.359548, 5.233607) (-2.341432, 5.241394) (-2.309206, 5.263473) (-2.295403, 5.277555) (-2.273972, 5.310216) (-2.266549, 5.328483) (-2.260836, 5.357986) (-2.259928, 5.368494) (-2.260326, 5.389526) (-2.26163, 5.399992) (-2.264018, 5.410236) knots 0 0 0 0 0.00585967 0.00585967 0.01171933 0.01171933 0.017579 0.017579 0.02343867 0.02343867 0.02929834 0.02929834 0.035158 0.035158 0.03831344 0.03831344 0.04146887 0.04146887 0.04146887 0.04146887
  spline S102 degree 5 poles (-2.532719, 5.289779) (-2.532839, 5.289949) (-2.534085, 5.291717) (-2.536467, 5.295076) (-2.540008, 5.300017) (-2.544748, 5.306517) (-2.550614, 5.314381) (-2.556569, 5.322198) (-2.562604, 5.329974) (-2.568709, 5.337713) (-2.574876, 5.34542) (-2.581101, 5.353096) (-2.587383, 5.360742) (-2.593724, 5.368358) (-2.600125, 5.37594) (-2.606588, 5.38349) (-2.613112, 5.391007) (-2.619694, 5.398491) (-2.626334, 5.405944) (-2.633028, 5.413368) (-2.639774, 5.420762) (-2.646572, 5.428129) (-2.653419, 5.435467) (-2.660318, 5.442777) (-2.667266, 5.450058) (-2.674264, 5.457312) (-2.681311, 5.464538) (-2.688406, 5.471736) (-2.695549, 5.478906) (-2.702738, 5.48605) (-2.709974, 5.493167) (-2.717254, 5.500258) (-2.72458, 5.507322) (-2.731949, 5.514361) (-2.739363, 5.521373) (-2.74682, 5.528359) (-2.754321, 5.53532) (-2.761864, 5.542255) (-2.769449, 5.549164) (-2.777076, 5.556048) (-2.784745, 5.562907) (-2.792454, 5.56974) (-2.800204, 5.576549) (-2.807994, 5.583333) (-2.815824, 5.590091) (-2.823693, 5.596825) (-2.831602, 5.603535) (-2.839549, 5.610219) (-2.847536, 5.616879) (-2.85556, 5.623515) (-2.863622, 5.630126) (-2.871723, 5.636713) (-2.87986, 5.643276) (-2.888035, 5.649814) (-2.896246, 5.656329) (-2.904494, 5.662819) (-2.912779, 5.669285) (-2.9211, 5.675727) (-2.929456, 5.682145) (-2.937848, 5.688539) (-2.946275, 5.694909) (-2.954738, 5.701255) (-2.963235, 5.707577) (-2.970061, 5.712616) (-2.975196, 5.716385) (-2.978626, 5.718892) (-2.980343, 5.720145) knots 0.1270499 0.1270499 0.1270499 0.1270499 0.1270499 0.1270499 0.12857143 0.14285714 0.15714286 0.17142857 0.18571429 0.2 0.21428571 0.22857143 0.24285714 0.25714286 0.27142857 0.28571429 0.3 0.31428571 0.32857143 0.34285714 0.35714286 0.37142857 0.38571429 0.4 0.41428571 0.42857143 0.44285714 0.45714286 0.47142857 0.48571429 0.5 0.51428571 0.52857143 0.54285714 0.55714286 0.57142857 0.58571429 0.6 0.61428571 0.62857143 0.64285714 0.65714286 0.67142857 0.68571429 0.7 0.71428571 0.72857143 0.74285714 0.75714286 0.77142857 0.78571429 0.8 0.81428571 0.82857143 0.84285714 0.85714286 0.87142857 0.88571429 0.9 0.91428571 0.92857143 0.94285714 0.95714286 0.97142857 0.98571429 1 1 1 1 1 1
  arc A34 (-2.980343, 5.720145) -> (-3.181274, 5.610882) centre (0, 0) ccw
  spline S103 degree 5 poles (-3.181274, 5.610882) (-3.181156, 5.60876) (-3.180916, 5.604518) (-3.180544, 5.598159) (-3.180025, 5.589691) (-3.179337, 5.579122) (-3.17861, 5.568569) (-3.177844, 5.558033) (-3.177039, 5.547514) (-3.176194, 5.537011) (-3.175309, 5.526525) (-3.174385, 5.516057) (-3.173421, 5.505606) (-3.172417, 5.495172) (-3.171372, 5.484757) (-3.170287, 5.474359) (-3.169161, 5.46398) (-3.167994, 5.453619) (-3.166786, 5.443276) (-3.165537, 5.432953) (-3.164246, 5.422648) (-3.162914, 5.412363) (-3.161539, 5.402097) (-3.160122, 5.391851) (-3.158663, 5.381625) (-3.15716, 5.371419) (-3.155615, 5.361234) (-3.154026, 5.351069) (-3.152394, 5.340925) (-3.150717, 5.330803) (-3.148997, 5.320702) (-3.147231, 5.310623) (-3.145421, 5.300566) (-3.143565, 5.290531) (-3.141663, 5.28052) (-3.139715, 5.270531) (-3.137721, 5.260566) (-3.13568, 5.250624) (-3.133592, 5.240706) (-3.131456, 5.230813) (-3.129271, 5.220945) (-3.127036, 5.211102) (-3.124751, 5.201286) (-3.122416, 5.191495) (-3.12003, 5.181732) (-3.117593, 5.171995) (-3.115105, 5.162286) (-3.112565, 5.152604) (-3.109973, 5.14295) (-3.107326, 5.133325) (-3.104622, 5.123732) (-3.101859, 5.11417) (-3.099035, 5.104642) (-3.096149, 5.095147) (-3.093204, 5.085685) (-3.090201, 5.076256) (-3.087142, 5.066858) (-3.084025, 5.057493) (-3.080847, 5.048162) (-3.077601, 5.03887) (-3.074276, 5.029623) (-3.070864, 5.020424) (-3.067985, 5.012912) (-3.065763, 5.007255) (-3.064237, 5.003429) (-3.063431, 5.001422) (-3.063353, 5.001229) knots -1 -1 -1 -1 -1 -1 -0.98571429 -0.97142857 -0.95714286 -0.94285714 -0.92857143 -0.91428571 -0.9 -0.88571429 -0.87142857 -0.85714286 -0.84285714 -0.82857143 -0.81428571 -0.8 -0.78571429 -0.77142857 -0.75714286 -0.74285714 -0.72857143 -0.71428571 -0.7 -0.68571429 -0.67142857 -0.65714286 -0.64285714 -0.62857143 -0.61428571 -0.6 -0.58571429 -0.57142857 -0.55714286 -0.54285714 -0.52857143 -0.51428571 -0.5 -0.48571429 -0.47142857 -0.45714286 -0.44285714 -0.42857143 -0.41428571 -0.4 -0.38571429 -0.37142857 -0.35714286 -0.34285714 -0.32857143 -0.31428571 -0.3 -0.28571429 -0.27142857 -0.25714286 -0.24285714 -0.22857143 -0.21428571 -0.2 -0.18571429 -0.17142857 -0.15714286 -0.14285714 -0.12857143 -0.1270499 -0.1270499 -0.1270499 -0.1270499 -0.1270499 -0.1270499
  spline S104 degree 3 poles (-3.310518, 4.841167) (-3.296962, 4.827105) (-3.28079, 4.815825) (-3.24503, 4.800098) (-3.225786, 4.795803) (-3.186734, 4.79483) (-3.167299, 4.798162) (-3.130801, 4.812088) (-3.114087, 4.822549) (-3.085609, 4.849289) (-3.074117, 4.865312) (-3.057923, 4.900862) (-3.053375, 4.920049) (-3.052233, 4.950077) (-3.05294, 4.960601) (-3.056543, 4.981326) (-3.059429, 4.991471) (-3.063353, 5.001229) knots 0 0 0 0 0.00585967 0.00585967 0.01171933 0.01171933 0.017579 0.017579 0.02343867 0.02343867 0.02929834 0.02929834 0.035158 0.035158 0.03831344 0.03831344 0.04146887 0.04146887 0.04146887 0.04146887
  spline S105 degree 5 poles (-3.310518, 4.841167) (-3.310662, 4.841317) (-3.312164, 4.842874) (-3.31503, 4.845831) (-3.319284, 4.850173) (-3.324961, 4.855872) (-3.331959, 4.862749) (-3.339037, 4.869566) (-3.346188, 4.876329) (-3.353403, 4.883046) (-3.360674, 4.889721) (-3.367998, 4.896357) (-3.375373, 4.902955) (-3.382803, 4.909513) (-3.390286, 4.916029) (-3.397826, 4.922504) (-3.40542, 4.928937) (-3.413068, 4.935329) (-3.420768, 4.941681) (-3.428517, 4.947996) (-3.436313, 4.954274) (-3.444155, 4.960516) (-3.452043, 4.966723) (-3.459976, 4.972894) (-3.467954, 4.97903) (-3.475977, 4.98513) (-3.484045, 4.991195) (-3.492155, 4.997226) (-3.500309, 5.003222) (-3.508505, 5.009185) (-3.516742, 5.015114) (-3.52502, 5.02101) (-3.533338, 5.026874) (-3.541695, 5.032705) (-3.550093, 5.038503) (-3.558529, 5.044269) (-3.567004, 5.050003) (-3.575517, 5.055705) (-3.584068, 5.061376) (-3.592657, 5.067015) (-3.601282, 5.072623) (-3.609944, 5.078199) (-3.618643, 5.083745) (-3.627377, 5.08926) (-3.636147, 5.094744) (-3.644952, 5.100198) (-3.653792, 5.105622) (-3.662667, 5.111015) (-3.671576, 5.116378) (-3.68052, 5.121711) (-3.689497, 5.127014) (-3.698507, 5.132287) (-3.707551, 5.137531) (-3.716628, 5.142744) (-3.725738, 5.147929) (-3.73488, 5.153084) (-3.744055, 5.158209) (-3.753261, 5.163306) (-3.762499, 5.168373) (-3.771769, 5.173411) (-3.78107, 5.17842) (-3.790402, 5.1834) (-3.799765, 5.188351) (-3.80728, 5.192289) (-3.81293, 5.195229) (-3.816703, 5.197184) (-3.818591, 5.19816) knots 0.1270499 0.1270499 0.1270499 0.1270499 0.1270499 0.1270499 0.12857143 0.14285714 0.15714286 0.17142857 0.18571429 0.2 0.21428571 0.22857143 0.24285714 0.25714286 0.27142857 0.28571429 0.3 0.31428571 0.32857143 0.34285714 0.35714286 0.37142857 0.38571429 0.4 0.41428571 0.42857143 0.44285714 0.45714286 0.47142857 0.48571429 0.5 0.51428571 0.52857143 0.54285714 0.55714286 0.57142857 0.58571429 0.6 0.61428571 0.62857143 0.64285714 0.65714286 0.67142857 0.68571429 0.7 0.71428571 0.72857143 0.74285714 0.75714286 0.77142857 0.78571429 0.8 0.81428571 0.82857143 0.84285714 0.85714286 0.87142857 0.88571429 0.9 0.91428571 0.92857143 0.94285714 0.95714286 0.97142857 0.98571429 1 1 1 1 1 1
  arc A35 (-3.818591, 5.19816) -> (-4.000488, 5.059506) centre (0, 0) ccw
  spline S106 degree 5 poles (-4.000488, 5.059506) (-4.000047, 5.057427) (-3.999162, 5.053271) (-3.997824, 5.047043) (-3.996018, 5.038753) (-3.993725, 5.028413) (-3.991396, 5.018095) (-3.989031, 5.0078) (-3.986629, 4.997526) (-3.984191, 4.987276) (-3.981716, 4.977048) (-3.979205, 4.966843) (-3.976657, 4.956662) (-3.974072, 4.946504) (-3.971449, 4.93637) (-3.96879, 4.92626) (-3.966093, 4.916174) (-3.963358, 4.906113) (-3.960585, 4.896076) (-3.957775, 4.886064) (-3.954926, 4.876077) (-3.952039, 4.866116) (-3.949113, 4.85618) (-3.946149, 4.846271) (-3.943146, 4.836387) (-3.940103, 4.82653) (-3.937021, 4.8167) (-3.933899, 4.806897) (-3.930738, 4.797121) (-3.927536, 4.787373) (-3.924293, 4.777653) (-3.92101, 4.767962) (-3.917685, 4.758299) (-3.914319, 4.748666) (-3.910912, 4.739062) (-3.907462, 4.729487) (-3.90397, 4.719943) (-3.900435, 4.71043) (-3.896857, 4.700947) (-3.893236, 4.691496) (-3.88957, 4.682077) (-3.88586, 4.67269) (-3.882103, 4.663338) (-3.878301, 4.654019) (-3.874452, 4.644734) (-3.870558, 4.635483) (-3.866616, 4.626267) (-3.862629, 4.617086) (-3.858593, 4.607941) (-3.854508, 4.598834) (-3.850371, 4.589766) (-3.846181, 4.580738) (-3.841935, 4.571752) (-3.837634, 4.562809) (-3.83328, 4.553908) (-3.828872, 4.545047) (-3.824414, 4.536227) (-3.819904, 4.527447) (-3.81534, 4.518711) (-3.810713, 4.510023) (-3.806015, 4.501391) (-3.801239, 4.492821) (-3.797247, 4.485837) (-3.794187, 4.480585) (-3.792096, 4.477037) (-3.790993, 4.475177) (-3.790886, 4.474998) knots -1 -1 -1 -1 -1 -1 -0.98571429 -0.97142857 -0.95714286 -0.94285714 -0.92857143 -0.91428571 -0.9 -0.88571429 -0.87142857 -0.85714286 -0.84285714 -0.82857143 -0.81428571 -0.8 -0.78571429 -0.77142857 -0.75714286 -0.74285714 -0.72857143 -0.71428571 -0.7 -0.68571429 -0.67142857 -0.65714286 -0.64285714 -0.62857143 -0.61428571 -0.6 -0.58571429 -0.57142857 -0.55714286 -0.54285714 -0.52857143 -0.51428571 -0.5 -0.48571429 -0.47142857 -0.45714286 -0.44285714 -0.42857143 -0.41428571 -0.4 -0.38571429 -0.37142857 -0.35714286 -0.34285714 -0.32857143 -0.31428571 -0.3 -0.28571429 -0.27142857 -0.25714286 -0.24285714 -0.22857143 -0.21428571 -0.2 -0.18571429 -0.17142857 -0.15714286 -0.14285714 -0.12857143 -0.1270499 -0.1270499 -0.1270499 -0.1270499 -0.1270499 -0.1270499
  spline S107 degree 3 poles (-4.010721, 4.279082) (-3.995177, 4.267254) (-3.977472, 4.258575) (-3.939732, 4.248492) (-3.920057, 4.247184) (-3.881314, 4.252184) (-3.862616, 4.258444) (-3.828671, 4.277778) (-3.81375, 4.290668) (-3.789687, 4.321442) (-3.780776, 4.339031) (-3.770199, 4.376636) (-3.768633, 4.396292) (-3.772088, 4.426143) (-3.774393, 4.436436) (-3.781117, 4.456368) (-3.785519, 4.465953) (-3.790886, 4.474998) knots 0 0 0 0 0.00585967 0.00585967 0.01171933 0.01171933 0.017579 0.017579 0.02343867 0.02343867 0.02929834 0.02929834 0.035158 0.035158 0.03831344 0.03831344 0.04146887 0.04146887 0.04146887 0.04146887
  spline S108 degree 5 poles (-4.010721, 4.279082) (-4.010886, 4.279209) (-4.012608, 4.280518) (-4.015892, 4.283002) (-4.020759, 4.286644) (-4.027239, 4.291411) (-4.035205, 4.297139) (-4.043241, 4.302795) (-4.051341, 4.308388) (-4.059496, 4.313924) (-4.0677, 4.319411) (-4.075951, 4.324851) (-4.084248, 4.330246) (-4.092591, 4.335593) (-4.100982, 4.340891) (-4.109421, 4.346139) (-4.117909, 4.351337) (-4.126443, 4.356486) (-4.135022, 4.361589) (-4.143644, 4.366647) (-4.152307, 4.371661) (-4.16101, 4.376633) (-4.169753, 4.381563) (-4.178535, 4.386451) (-4.187356, 4.391297) (-4.196217, 4.396101) (-4.205115, 4.400864) (-4.214052, 4.405586) (-4.223025, 4.410267) (-4.232035, 4.414909) (-4.241081, 4.419511) (-4.250162, 4.424075) (-4.259277, 4.4286) (-4.268427, 4.433086) (-4.277611, 4.437535) (-4.286829, 4.441946) (-4.29608, 4.446319) (-4.305364, 4.450654) (-4.31468, 4.454953) (-4.324029, 4.459215) (-4.333409, 4.46344) (-4.342821, 4.46763) (-4.352264, 4.471783) (-4.361738, 4.4759) (-4.371242, 4.479981) (-4.380776, 4.484027) (-4.390341, 4.488037) (-4.399935, 4.492012) (-4.409558, 4.495952) (-4.419211, 4.499858) (-4.428892, 4.503728) (-4.438602, 4.507564) (-4.448341, 4.511366) (-4.458107, 4.515133) (-4.467902, 4.518866) (-4.477724, 4.522565) (-4.487573, 4.52623) (-4.497449, 4.529861) (-4.507353, 4.533459) (-4.517283, 4.537023) (-4.527239, 4.540554) (-4.537222, 4.544051) (-4.547231, 4.547515) (-4.555259, 4.550259) (-4.561292, 4.552303) (-4.565319, 4.553658) (-4.567334, 4.554334) knots 0.1270499 0.1270499 0.1270499 0.1270499 0.1270499 0.1270499 0.12857143 0.14285714 0.15714286 0.17142857 0.18571429 0.2 0.21428571 0.22857143 0.24285714 0.25714286 0.27142857 0.28571429 0.3 0.31428571 0.32857143 0.34285714 0.35714286 0.37142857 0.38571429 0.4 0.41428571 0.42857143 0.44285714 0.45714286 0.47142857 0.48571429 0.5 0.51428571 0.52857143 0.54285714 0.55714286 0.57142857 0.58571429 0.6 0.61428571 0.62857143 0.64285714 0.65714286 0.67142857 0.68571429 0.7 0.71428571 0.72857143 0.74285714 0.75714286 0.77142857 0.78571429 0.8 0.81428571 0.82857143 0.84285714 0.85714286 0.87142857 0.88571429 0.9 0.91428571 0.92857143 0.94285714 0.95714286 0.97142857 0.98571429 1 1 1 1 1 1
  arc A36 (-4.567334, 4.554334) -> (-4.725934, 4.389539) centre (0, 0) ccw